M2Standoff (Autodesk Fusion 360 design; units mm, degrees)
Autodesk Fusion 360 part; units mm, degrees
sketch "Sketch1" plane through (0, 0, 0) normal (0, 1, 0) x (1, 0, 0)
  circle A0 centre (0, 0) radius 1
  circle A1 centre (0, 0) radius 2.2
  line L0 (0, 0) -> (2.2, 0)
  line L1 (0, 0) -> (1.1, -1.9053)
  line L2 (0, 0) -> (2.2, 0) construction
  line L3 (0, 0) -> (1.1, 1.9053)
  line L4 (0, 0) -> (-1.1, 1.9053)
  line L5 (0, 0) -> (-1.1, -1.9053)
  line L6 (0, 0) -> (-2.2, 0)
  line L7 (1.1, -1.9053) -> (2.2, 0)
  line L8 (2.2, 0) -> (1.1, 1.9053)
  line L9 (1.1, 1.9053) -> (-1.1, 1.9053)
  line L10 (-1.1, 1.9053) -> (-2.2, 0)
  line L11 (-2.2, 0) -> (-1.1, -1.9053)
  line L12 (-1.1, -1.9053) -> (1.1, -1.9053)
  dimension "d1" = 2
  dimension "d3" = 60
  dimension "d4" = 60
  constraint coincident A0.centre A1.centre
  constraint concentric A0 A1
  constraint coincident A1 L0.end
  constraint horizontal L0
  constraint coincident A1 L1.end
  constraint horizontal L2
  constraint coincident A1 L3.end
  constraint coincident A1 L4.end
  constraint parallel L1 L4
  constraint coincident A1 L5.end
  constraint parallel L3 L5
  constraint coincident A1 L6.end
  constraint horizontal L6
  constraint parallel L5 L7
  measures "d1" diameter of A0
  measures "d3" angle of L1 L2
  measures "d4" angle of L2 L3
extrude "Extrude1" add sketch "Sketch1" along normal blind 9 contours A0 L0 L1 L7 | A0 L0 L3 L8 | A0 L3 L4 L9 | A0 L1 L5 L12 | A0 L4 L6 L10 | A0 L5 L6 L11
sketch "Sketch2" plane through (0, 0, 0) normal (0, -1, 0) x (1, 0, 0)
  circle A0 centre (0, 0) radius 1
  line L0 (1.1, 1.9053) -> (-1.1, 1.9053)
  line L1 (-1.1, 1.9053) -> (-2.2, 0)
  line L2 (-2.2, 0) -> (-1.1, -1.9053)
  line L3 (-1.1, -1.9053) -> (1.1, -1.9053)
  line L4 (1.1, -1.9053) -> (2.2, 0)
  line L5 (2.2, 0) -> (1.1, 1.9053)
extrude "Extrude2" add sketch "Sketch2" against normal blind 4.5 contours A0
sketch "Sketch3" plane through (0, 0, 0) normal (0, -1, 0) x (1, 0, 0)
  line L0 (1.1, 1.9053) -> (-1.1, 1.9053)
  line L1 (-1.1, 1.9053) -> (-2.2, 0)
  line L2 (-2.2, 0) -> (-1.1, -1.9053)
  line L3 (-1.1, -1.9053) -> (1.1, -1.9053)
  line L4 (1.1, -1.9053) -> (2.2, 0)
  line L5 (2.2, 0) -> (1.1, 1.9053)
  circle A0 centre (0, 0) radius 1
  dimension "d9" = 2
  constraint coincident A0.centre origin
  measures "d9" diameter of A0
extrude "Extrude3" add sketch "Sketch3" along normal blind 3.2 contours A0
thread "Thread2" "ISO Metric profile 2.0 M2x0.4 6g" major diameter 1.9335 minor diameter 1.478 pitch 0.4 angle 60 modelled right hand crest width 0.05 on face at (0.995, -2.1333, -0.0996) crest through (0.9668, 0.025, 0)
thread "Thread1" [suppressed]
